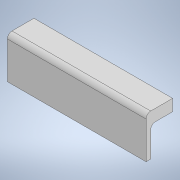
# Autodesk Inventor part: balama_sus
Saved by Autodesk Inventor 2022.6 (Build 266554000, 554)
## iProperties
Created: 2025-03-07
Part Number: balama_sus
Material: Generic
Document SubType Name: Modeling
Designer: Dragos Macovei
Density: 1 g/cm^3
Appearance: Default
Author: Dragos Macovei
Autodesk Inventor part; units mm, degrees
ref_plane "YZ Plane" through (0, 0, 0) normal (1, 0, 0) x (0, 1, 0)
ref_plane "XZ Plane" through (0, 0, 0) normal (0, 1, 0) x (-1, 0, 0)
ref_plane "XY Plane" through (0, 0, 0) normal (0, 0, 1) x (1, 0, 0)
sketch "Sketch1" plane through (0, 0, 0) normal (0, 0, 1) x (1, 0, 0)
  line L0 (0, 0) -> (-60, 0)
  line L1 (-60, 0) -> (-60, 13)
  line L2 (-60, 13) -> (0, 13)
  line L3 (0, 13) -> (0, 0)
  dimension "d0" = 60
  dimension "d1" = 13
  constraints: 8 end point, 2 parallel, 1 horizontal, 1 perpendicular
  measures "d0" distance of L1.end L2.end
  measures "d1" distance of L0.end L1.end
extrude "Extrusion1" add sketch "Sketch1" along normal blind 2
sketch "Sketch2" plane through (-60, 13, 0) normal (0, 1, 0) x (1, 0, 0)
  line L0 (60, -2) -> (0, -2) projected
  line L1 (0, -2) -> (60, -2)
  line L2 (60, -2) -> (60, 9.5)
  line L3 (60, 9.5) -> (0, 9.5)
  line L4 (0, 9.5) -> (0, -2)
  point P0 (60, 0)
  dimension "d4" = 11.5
  constraints: 8 end point, 2 parallel, 1 horizontal, 1 perpendicular
  measures "d4" distance of L2.end L1.end
extrude "Extrusion2" add sketch "Sketch2" along normal blind 5
fillet "Fillet1" radius 2 2 edges at (-30, 13, 0) (-30, 18, 2)
body "Solid1"
